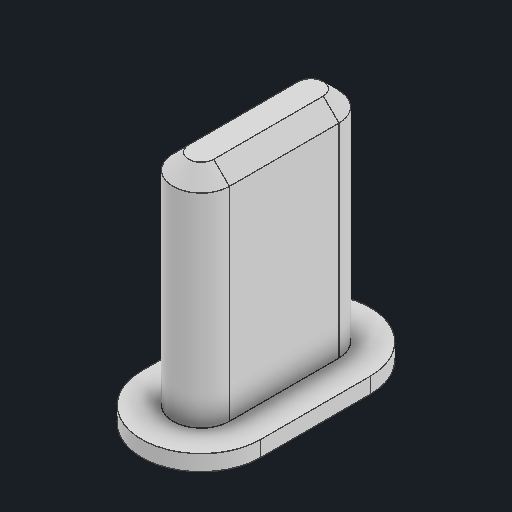
# Autodesk Inventor part: sw
Saved by Autodesk Inventor 2027 (Build 310192000, 192)
## iProperties
Created: 2026-10-19
Part Number: sw
Material: 일반
Document SubType Name: Modeling
Designer: khw
Density: 1 g/cm^3
Appearance: 기본값
Author: khw
Autodesk Inventor part; units mm, degrees
ref_plane "YZ Plane" through (0, 0, 0) normal (1, 0, 0) x (0, 1, 0)
ref_plane "XZ Plane" through (0, 0, 0) normal (0, 1, 0) x (-1, 0, 0)
ref_plane "XY Plane" through (0, 0, 0) normal (0, 0, 1) x (1, 0, 0)
sketch "스케치1" plane through (0, 0, 0) normal (0, 1, 0) x (-1, 0, 0)
  line L0 (0, 0) -> (0, -3.5) construction
  line L1 (-1.9, 0) -> (-1.9, -3.5)
  line L2 (1.9, -3.5) -> (1.9, 0)
  arc A0 (1.9, 0) -> (-1.9, 0) centre (0, 0) ccw
  arc A1 (-1.9, -3.5) -> (1.9, -3.5) centre (0, -3.5) ccw
  line L3 (0, 0) -> (0, -3.5) construction
  line L4 (-0.9, 0) -> (-0.9, -3.5)
  line L5 (0.9, -3.5) -> (0.9, 0)
  arc A2 (0.9, 0) -> (-0.9, 0) centre (0, 0) ccw
  arc A3 (-0.9, -3.5) -> (0.9, -3.5) centre (0, -3.5) ccw
  point P0 (0, -1.75)
  point P1 (0, -1.75)
  dimension "d0" = 3.8
  dimension "d1" = 3.5
  dimension "d2" = 0.9
  constraints: 16 end point, 8 point on circle, 8 tangent, 4 centre point, 2 midpoint, 2 parallel, 2 vertical
  measures "d0" distance between parallel lines of L1 L2
  measures "d1" distance of L0.start L0.end
  measures "d2" radius of A2
extrude "돌출1" add sketch "스케치1" along normal blind 0.5
extrude "돌출2" add sketch "스케치1" along normal blind 7.5 contours A2 L5 A3 L4
chamfer "모따기1" distance 0.5 angle 45 4 edges at (0.9, 7.5, -1.75) (0, 7.5, -4.4) (-0.9, 7.5, -1.75) (0, 7.5, 0.9)
